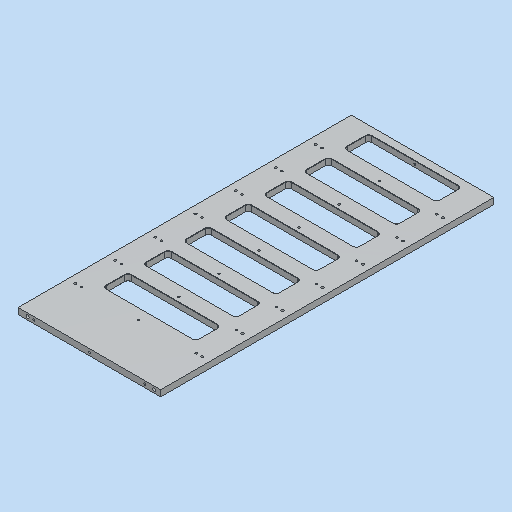
# Autodesk Inventor part: MM0948AN130_G01_113
Saved by Autodesk Inventor 2023.3 (Build 273359000, 359)
## iProperties
Part Number: MM0948AN130_G01_113
Material: 3.3547 AlMg4,5Mn0,7 - AW 5083
Description: =<RBPARTNOTITLE2>
Document SubType Name: Modeling
Designer: ric7an
Mass: 2223.19 g
Surface Area: 2102.43 cm^2
Volume: 823.403 cm^3
Density: 2.7 g/cm^3
Appearance: Aluminium AnP
Created: 2023-03-23
RBDOCUMENTTYPE: DRF
RBDOCUMENTVERSION: 00
RBDRAWINGMAINSCALE: 1:1
RBDRAWINGMISSINGSPEC: --
RBDRAWINGVOLUME: --
RBGBEDGESIN1: +0,5
RBGBEDGESIN2: +0,2
RBGBEDGESOUT1: -0,3
RBGBEDGESOUT2: -0,1
RBMATERIAL: =<Material>
RBMATMEETS: --
RBMATNO: =<Part Number>
RBPARTMADEOF: 10 x 540 x 276 (FM)
RBPARTNO: SIEHE MNR
RBPARTNOTITLE1: manufactured part
RBPARTNOTITLE2: Anfertigungsteil
RBPARTSAFETYINDICATOR: --
RBSURFACE: anodised colourless
RBSURFACE2: eloxiert farblos
RBZEDGESNORM: ISO13715:2002-06
RBZGENDIMCLASS: m
RBZGENDIMNORM: ISO 2768-1:1989-11
RBZGENGEOCLASS: H
RBZGENGEONORM: ISO 2768-2:1989-11
RBZSURFACENORM: ISO13D2:2002-02
RBZTOLERANCENORM: ISO 14405-1:2010-12
AnP_Material: =<Material>
AnP_TemplVers: 20190222
AnP_Kategorie: 1
MaxAbmaße: 10 x 540 x 276 (FM)
AnP_Kommentar_aktuell: =<Comments>
AnP_Material_aktuell: =<Material>
Author: FH/Wi
Keywords: =<RBPARTMADEOF>
Comments: =<RBSURFACE2>
Revision Number: 01
Autodesk Inventor part; units mm, degrees
ref_plane "YZ Plane" through (0, 0, 0) normal (1, 0, 0) x (0, 1, 0)
ref_plane "XZ Plane" through (0, 0, 0) normal (0, 1, 0) x (-1, 0, 0)
sketch "Skizze1" plane through (0, 0, 0) normal (0, 0, 1) x (1, 0, 0)
  line L0 (0, 0) -> (231, 0)
  line L1 (231, 0) -> (231, 540)
  line L2 (231, 540) -> (0, 540)
  line L3 (0, 540) -> (0, 0)
  line L4 (0, 648) -> (0, -108) projected
  line L5 (-46.2, 0) -> (277.2, 0) projected
  point P0 (0, 0)
  dimension "d0" = 540
  dimension "d1" = 231
  constraints: 8 end point, 2 collinear, 2 parallel, 1 horizontal, 1 perpendicular
  measures "d0" distance of L0.end L1.end
  measures "d1" distance of L1.end L2.end
extrude "Extrusion1" add sketch "Skizze1" against normal blind 10
ref_plane "Arbeitsebene1" through (0, 40, -2.5) normal (0, 0, 1) x (1, 0, 0)
sketch "Skizze4" plane through (0, 40, 0) normal (0, 0, 1) x (1, 0, 0)
  line L0 (231, 500) -> (0, 500) projected
  line L1 (0, -40) -> (231, -40) projected
  point P0 (22.5, 430)
  point P1 (218.5, 430)
  point P2 (208.5, 430)
  point P3 (115.5, 430)
  point P4 (12.5, 430)
  point P5 (115.5, 500)
  dimension "d18" = 93
  dimension "d20" = 10
  dimension "d42" = 10
  dimension "d43" = 186
  dimension "d69" = 470
  constraints: 4 horizontal alignment, 1 midpoint, 1 vertical alignment
  measures "d18" distance of point (115.5, 430) point (22.5, 430)
  measures "d20" distance of point (218.5, 430) point (208.5, 430)
  measures "d42" distance of point (22.5, 430) point (12.5, 430)
  measures "d43" distance of point (208.5, 430) point (22.5, 430)
  measures "d69" distance from line of L1 point (12.5, 430)
hole "Bohrung1" at (22.5, 470, 0) at (208.5, 470, 0) at (115.5, 470, 0) direction (0, 0, -1) diameter 3.242 end through all thread size "M4x0.7" designation "M4" class "6H" standard "ISO Metric profile"
hole "Bohrung2" at (218.5, 470, 0) at (12.5, 470, 0) direction (0, 0, -1) diameter 4 end through all
sketch "Skizze7" plane through (0, 0, 0) normal (0, 0, 1) x (1, 0, 0)
  line L0 (40.5, 527.5) -> (190.5, 527.5)
  line L1 (190.5, 527.5) -> (190.5, 487.5)
  line L2 (190.5, 487.5) -> (40.5, 487.5)
  line L3 (40.5, 487.5) -> (40.5, 527.5)
  line L4 (-48.6, 0) -> (291.6, 0) projected
  line L5 (231, 540) -> (0, 540) projected
  line L6 (40.5, 507.5) -> (190.5, 507.5) construction
  circle A0 centre (218.5, 470) radius 2 projected
  point P0 (0, 0)
  point P1 (115.5, 527.5)
  point P2 (115.5, 540)
  dimension "d60" = 150
  dimension "d61" = 40
  dimension "d163" = 17.5
  constraints: 10 end point, 4 midpoint, 2 parallel, 1 horizontal, 1 perpendicular, 1 vertical alignment
  measures "d60" distance of L0.start L0.end
  measures "d61" distance of L0.end L1.end
  measures "d163" distance from line of A0.centre L2
extrude "Extrusion6" cut sketch "Skizze7" against normal through all contours L0 L1 L2 L3
fillet "Rundung2" radius 5 4 edges at (40.5, 527.5, -5) (40.5, 487.5, -5) (190.5, 487.5, -5) (190.5, 527.5, -5)
sketch "Skizze8" plane through (0, 0, 0) normal (0, -1, 0) x (1, 0, 0)
  line L0 (231, -10) -> (0, -10) projected
  line L1 (0, 0) -> (0, -10) projected
  line L2 (231, 0) -> (231, -10) projected
  line L3 (25.5, -5) -> (205.5, -5)
  point P0 (115.5, -5)
  dimension "d71" = 5
  dimension "d72" = 180
  dimension "d90" = 231
  dimension "d91" = 25.5
  constraints: 2 end point, 1 horizontal, 1 horizontal alignment, 1 midpoint
  measures "d71" distance from line of L0 L3.start
  measures "d72" distance of L3.end L3.start
  measures "d90" distance between parallel lines of L2 L1
  measures "d91" distance from line of L3.start L1
hole "Bohrung3" at (25.5, 0, -5) at (205.5, 0, -5) at (115.5, 0, -5) direction (0, 1, 0) diameter 3.242 depth 15 tip angle 118 thread size "M4x0.7" designation "M4" class "6H" standard "ISO Metric profile"
sketch "Skizze9" plane through (0, 0, 0) normal (0, -1, 0) x (1, 0, 0)
  circle A0 centre (25.5, -5) radius 1.621 projected
  circle A1 centre (205.5, -5) radius 1.621 projected
  point P0 (0, 0)
  point P1 (15.5, -5)
  point P2 (220.5, -5)
  dimension "d92" = 10
  dimension "d187" = 15
  constraints: 2 horizontal alignment
  measures "d92" distance of A0.centre point (15.5, -5)
  measures "d187" distance of point (220.5, -5) A1.centre
hole "Bohrung4" at (15.5, 0, -5) at (220.5, 0, -5) direction (0, 1, 0) diameter 5 depth 10 tip angle 118
sketch "Skizze10" plane through (0, 540, 0) normal (0, 1, 0) x (1, 0, 0)
  line L0 (231, 0) -> (0, 0) projected
  line L1 (231, 0) -> (231, 10) projected
  line L2 (0, 0) -> (0, 10) projected
  line L3 (15.5, 5) -> (215.5, 5)
  point P0 (115.5, 5)
  dimension "d93" = 5
  dimension "d94" = 200
  dimension "d95" = 231
  dimension "d96" = 15.5
  constraints: 2 end point, 1 horizontal, 1 horizontal alignment, 1 midpoint
  measures "d93" distance from line of L0 L3.start
  measures "d94" distance of L3.end L3.start
  measures "d95" distance between parallel lines of L1 L2
  measures "d96" distance from line of L3.start L2
hole "Bohrung5" at (15.5, 540, -5) at (215.5, 540, -5) at (115.5, 540, -5) direction (0, -1, 0) diameter 3.242 depth 15 tip angle 118 thread size "M4x0.7" designation "M4" class "6H" standard "ISO Metric profile"
chamfer "Fase1" distance 0.5 angle 45 16 edges at (40.5, 507.5, -10) (41.9645, 488.9645, -10) (115.5, 487.5, -10) (189.0355, 488.9645, -10) (190.5, 507.5, -10) (189.0355, 526.0355, -10) (115.5, 527.5, -10) (41.9645, 526.0355, -10) (40.5, 507.5, 0) (41.9645, 526.0355, 0) (115.5, 527.5, 0) (189.0355, 526.0355, 0) (190.5, 507.5, 0) (189.0355, 488.9645, 0) (115.5, 487.5, 0) (41.9645, 488.9645, 0)
sketch "Skizze11" plane through (0, 540, 0) normal (0, 1, 0) x (1, 0, 0)
  circle A0 centre (15.5, 5) radius 1.621 projected
  circle A1 centre (215.5, 5) radius 1.621 projected
  point P0 (0, 0)
  point P1 (30.5, 5)
  dimension "d107" = 200
  dimension "d191" = 15
  constraints: 1 horizontal alignment
  measures "d107" distance of A1.centre A0.centre
  measures "d191" distance of point (30.5, 5) A0.centre
hole "Bohrung6" at (30.5, 540, -5) direction (0, -1, 0) diameter 5 depth 10 tip angle 118
pattern_linear "Rechteckige Anordnung2" count 7 spacing 65 along (0, -1, 0) of "Bohrung2", "Bohrung1", "Rundung2", "Fase1", "Extrusion6"
equation "\"d18\" = 0.5 * d43"
equation "\"d91\" = -0.5 * d72 + 0.5 * d90"
equation "\"d96\" = -0.5 * d94 + 0.5 * d95"
